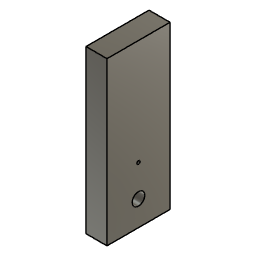
ensamble_pata (Autodesk Fusion 360 archive; units mm, degrees)
design "pierna"
Autodesk Fusion 360 part; units mm, degrees
sketch "Sketch1" plane through (0, 0, 0) normal (1, 0, 0) x (0, 1, 0)
  line L0 (0, 0) -> (30, 0)
  line L1 (30, 0) -> (30, 77.1664)
  line L2 (30, 77.1664) -> (0, 77.1664)
  line L3 (0, 77.1664) -> (0, 0)
  dimension "d1" = 30
  constraint horizontal L0
  constraint vertical L1
  constraint horizontal L2
  constraint vertical L3
  constraint coincident L0.start L3.end
  measures "d1" distance of L0.start L0.end
extrude "Extrude1" add sketch "Sketch1" along normal blind 10
sketch "Sketch2" plane through (10, 0, 0) normal (1, 0, 0) x (0, 1, 0)
  line L0 (0, 77.1664) -> (0, 0)
  line L1 (0, 0) -> (30, 0)
  line L2 (30, 0) -> (30, 77.1664)
  line L3 (30, 77.1664) -> (0, 77.1664)
  point P0 (15, 11.8696)
  point P1 (15, 26.8696)
  dimension "d7" = 15
  measures "d7" distance of P0 P1
hole "Hole1" at (10, 15, 11.8696) direction (-1, 0, 0) diameter 6 depth 30 tip angle 118
hole "Hole2" at (10, 15, 26.8696) direction (-1, 0, 0) diameter 1.5 depth 3 tip angle 118
